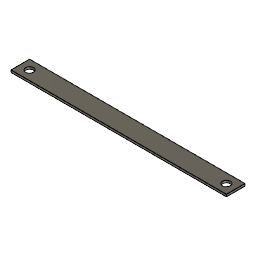
Wireless charger coil mount (Autodesk Fusion 360 design; units mm, degrees)
Autodesk Fusion 360 part; units mm, degrees
sketch "Sketch1" plane through (0, 0, 0) normal (0, 0, 1) x (1, 0, 0)
  line L0 (0, 0) -> (115, 0)
  line L1 (115, 0) -> (115, 10)
  line L2 (115, 10) -> (0, 10)
  line L3 (0, 10) -> (0, 0)
  dimension "d1" = 115
  dimension "d2" = 10
  constraint horizontal L0
  constraint vertical L1
  constraint horizontal L2
  constraint vertical L3
  constraint coincident L0.start L3.end
  measures "d1" distance of L0.start L0.end
  measures "d2" distance of L0.start L2.end
extrude "Extrude1" add sketch "Sketch1" along normal blind 1
extrude "Extrude2" add 1 faces at (38.3333, 3.3333, 1) along direction (0, 0, 1) blind 0.2
sketch "Sketch2" plane through (0, 0, 1.2) normal (0, 0, 1) x (-1, 0, 0)
  line L0 (0, -10) -> (0, 0)
  line L1 (0, 0) -> (-115, 0)
  line L2 (-115, 0) -> (-115, -10)
  line L3 (-115, -10) -> (0, -10)
  line L4 (-5, -5) -> (-110, -5)
  circle A0 centre (-5, -5) radius 2.1
  circle A1 centre (-110, -5) radius 2.1
  point P0 (-57.5, -5)
  dimension "d7" = 105
  dimension "d8" = 4.2
  dimension "d9" = 4.2
  constraint midpoint L4 P0
  constraint perpendicular L2 L4
  constraint coincident L4.start A0.centre
  constraint coincident L4.end A1.centre
  measures "d7" distance of L4.start L4.end
  measures "d8" diameter of A0
  measures "d9" diameter of A1
extrude "Extrude3" cut sketch "Sketch2" against normal blind 1.2 contours A0 | A1
